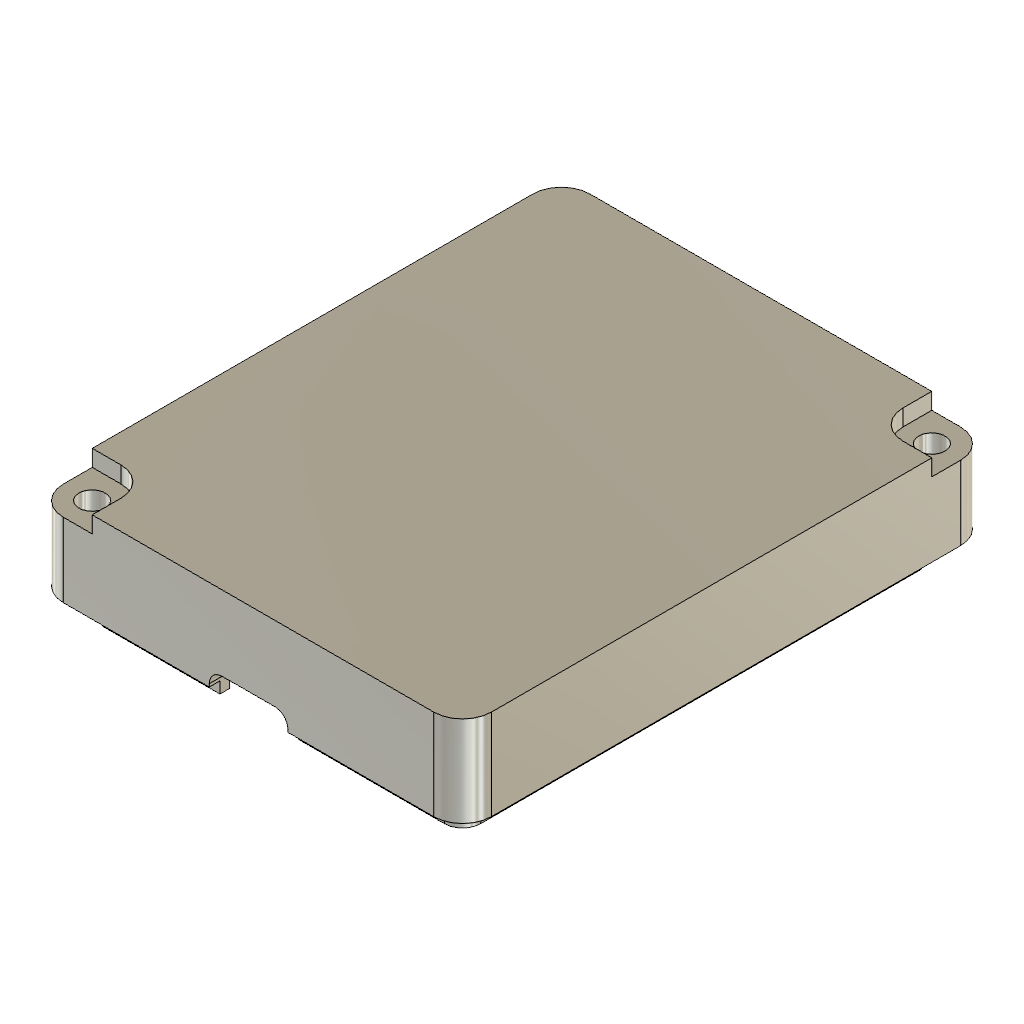
enclosure-Nov13 (Autodesk Fusion 360 archive; units mm, degrees)
design "lid-usb"
Autodesk Fusion 360 part; units mm, degrees
sketch "Sketch1" plane through (0, 0, 0) normal (0, 0, 1) x (1, 0, 0)
  circle A0 centre (22.5, -0.75) radius 1.55
  line L0 (22.5, -58.75) -> (-19, -58.75)
  arc A1 (-19, -57.75) -> (-22.5, -54.25) centre (-22.5, -57.75) ccw
  arc A2 (23.5, -57.75) -> (22.5, -58.75) centre (22.5, -57.75) cw
  arc A3 (-23.5, -0.75) -> (-22.5, 0.25) centre (-22.5, -0.75) cw
  arc A4 (19, -0.75) -> (22.5, -4.25) centre (22.5, -0.75) ccw
  line L1 (-22.5, 0.25) -> (19, 0.25)
  line L2 (22.5, -4.25) -> (23.5, -4.25)
  line L3 (-22.5, -54.25) -> (-23.5, -54.25)
  line L4 (-23.5, -54.25) -> (-23.5, -0.75)
  line L5 (19, 0.25) -> (19, -0.75)
  line L6 (-19, -58.75) -> (-19, -57.75)
  line L7 (23.5, -4.25) -> (23.5, -57.75)
  line L8 (22.5, 2.75) -> (-22.5, 2.75)
  arc A5 (26, -0.75) -> (22.5, 2.75) centre (22.5, -0.75) ccw
  arc A6 (-22.5, 2.75) -> (-26, -0.75) centre (-22.5, -0.75) ccw
  line L9 (-26, -0.75) -> (-26, -57.75)
  arc A7 (-26, -57.75) -> (-22.5, -61.25) centre (-22.5, -57.75) ccw
  arc A8 (22.5, -61.25) -> (26, -57.75) centre (22.5, -57.75) ccw
  line L10 (26, -57.75) -> (26, -0.75)
  line L11 (-22.5, -61.25) -> (22.5, -61.25)
  circle A9 centre (-22.5, -57.75) radius 1.55
  line L12 (-24.8, -0.75) -> (-24.8, -57.75)
  arc A10 (-22.5, 1.55) -> (-24.8, -0.75) centre (-22.5, -0.75) ccw
  line L13 (24.8, -57.75) -> (24.8, -0.75)
  line L14 (22.5, 1.55) -> (-22.5, 1.55)
  line L15 (-22.5, -60.05) -> (22.5, -60.05)
  arc A11 (22.5, -60.05) -> (24.8, -57.75) centre (22.5, -57.75) ccw
  arc A12 (-24.8, -57.75) -> (-22.5, -60.05) centre (-22.5, -57.75) ccw
  arc A13 (24.8, -0.75) -> (22.5, 1.55) centre (22.5, -0.75) ccw
  line L16 (23.5, -4.25) -> (24.8, -4.25)
  line L17 (19, 0.25) -> (19, 1.55)
  line L18 (-19, -58.75) -> (-19, -60.05)
  line L19 (-23.5, -54.25) -> (-24.8, -54.25)
  line L20 (5, -60.05) -> (5, -58.75)
  line L21 (-5, -60.05) -> (-5, -58.75)
  line L22 (24.8, -4.25) -> (26, -4.25)
  line L23 (19, 1.55) -> (19, 2.75)
  line L24 (-19, -60.05) -> (-19, -61.25)
  line L25 (-24.8, -54.25) -> (-26, -54.25)
  line L26 (-17, -58.75) -> (-17, -57.75)
  arc A14 (-17, -57.75) -> (-22.5, -52.25) centre (-22.5, -57.75) ccw
  line L27 (-22.5, -52.25) -> (-23.5, -52.25)
  line L28 (17, 0.25) -> (17, -0.75)
  arc A15 (17, -0.75) -> (22.5, -6.25) centre (22.5, -0.75) ccw
  line L29 (22.5, -6.25) -> (23.5, -6.25)
  point P0 (0, -60.05)
  dimension "d22" = 2
  dimension "d23" = 2
  constraint coincident L13 L16.end
  constraint coincident L10 L22.end
  constraint perpendicular L10 L22
  constraint coincident L8 L23.end
  constraint perpendicular L8 L23
  constraint coincident L11 L24.end
  constraint perpendicular L11 L24
  constraint coincident L9 L25.end
  constraint perpendicular L9 L25
extrude "Extrude1" add sketch "Sketch1" against normal blind 2 contours A0 | L0 A2 L7 L13 L15 A11 L16 L20 | L0 A2 A3 L1 L4 L7 L26 A14 L27 L28 A15 L29 | L0 L15 L20 L21 | L0 L15 L18 L21 | A8 L10 L11 L13 L15 A11 L22 L24 | A4 L1 L2 L5 L7 L28 A15 L29 | L0 A1 L3 L4 L6 L26 A14 L27 | A4 L2 L5 L13 L14 A13 L16 L17 | A1 L3 L6 L12 L15 A12 L18 L19 | L9 A7 L11 L12 L15 A12 L24 L25 | L8 A5 L10 L13 L14 A13 L22 L23 | A3 L1 L4 L12 A10 L14 L17 L19 | L8 A6 L9 L12 A10 L14 L23 L25 | A9
extrude "Extrude3" add sketch "Sketch1" against normal blind 11 contours L0 A2 L7 L13 L15 A11 L16 L20 | L0 L15 L20 L21 | L0 L15 L18 L21 | A8 L10 L11 L13 L15 A11 L22 L24 | A4 L2 L5 L13 L14 A13 L16 L17 | A1 L3 L6 L12 L15 A12 L18 L19 | L9 A7 L11 L12 L15 A12 L24 L25 | L8 A5 L10 L13 L14 A13 L22 L23 | A3 L1 L4 L12 A10 L14 L17 L19 | L8 A6 L9 L12 A10 L14 L23 L25
hole "Hole1" at (-22.5, -57.75, 0) at (22.5, -0.75, 0) direction (0, 0, -1) diameter 3.2 depth 12 tip angle 118
sketch "Sketch4" plane through (0, 0, -11) normal (0, 0, -1) x (1, 0, 0)
  circle A0 centre (-22.5, 57.75) radius 1.6
  circle A1 centre (22.5, 0.75) radius 1.6
  line L0 (23.5, 4.25) -> (22.5, 4.25)
  arc A2 (22.5, 4.25) -> (19, 0.75) centre (22.5, 0.75) ccw
  line L1 (19, 0.75) -> (19, -0.25)
  line L2 (19, -0.25) -> (-22.5, -0.25)
  arc A3 (-23.5, 0.75) -> (-22.5, -0.25) centre (-22.5, 0.75) ccw
  line L3 (-23.5, 0.75) -> (-23.5, 54.25)
  line L4 (-23.5, 54.25) -> (-22.5, 54.25)
  arc A4 (-22.5, 54.25) -> (-19, 57.75) centre (-22.5, 57.75) ccw
  line L5 (-19, 57.75) -> (-19, 58.75)
  line L6 (-19, 58.75) -> (22.5, 58.75)
  arc A5 (23.5, 57.75) -> (22.5, 58.75) centre (22.5, 57.75) ccw
  line L7 (23.5, 57.75) -> (23.5, 4.25)
  line L8 (22.5, 61.25) -> (-22.5, 61.25)
  arc A6 (-22.5, 61.25) -> (-26, 57.75) centre (-22.5, 57.75) ccw
  line L9 (-26, 57.75) -> (-26, 0.75)
  arc A7 (-26, 0.75) -> (-22.5, -2.75) centre (-22.5, 0.75) ccw
  line L10 (-22.5, -2.75) -> (22.5, -2.75)
  arc A8 (22.5, -2.75) -> (26, 0.75) centre (22.5, 0.75) ccw
  line L11 (26, 0.75) -> (26, 57.75)
  arc A9 (26, 57.75) -> (22.5, 61.25) centre (22.5, 57.75) ccw
  line L12 (-24.7, 57.75) -> (-24.7, 0.75)
  arc A10 (-24.7, 0.75) -> (-22.5, -1.45) centre (-22.5, 0.75) ccw
  line L13 (-22.5, -1.45) -> (22.5, -1.45)
  arc A11 (22.5, -1.45) -> (24.7, 0.75) centre (22.5, 0.75) ccw
  line L14 (24.7, 0.75) -> (24.7, 57.75)
  arc A12 (24.7, 57.75) -> (22.5, 59.95) centre (22.5, 57.75) ccw
  line L15 (22.5, 59.95) -> (-22.5, 59.95)
  arc A13 (-22.5, 59.95) -> (-24.7, 57.75) centre (-22.5, 57.75) ccw
  line L16 (-19, 58.75) -> (-19, 59.95)
  line L17 (-23.5, 54.25) -> (-24.7, 54.25)
  line L18 (19, -0.25) -> (19, -1.45)
  line L19 (23.5, 4.25) -> (24.7, 4.25)
  dimension "d27" = -1.3
  constraint coincident L5.end L6.start
  constraint coincident L15 L16.end
  constraint perpendicular L15 L16
  constraint coincident L3.end L4.start
  constraint coincident L12 L17.end
  constraint perpendicular L12 L17
  constraint coincident L1.end L2.start
  constraint coincident L13 L18.end
  constraint perpendicular L13 L18
  constraint coincident L0.start L7.end
  constraint coincident L14 L19.end
  constraint perpendicular L14 L19
extrude "Extrude9" add sketch "Sketch4" along normal blind 1.4 contours L6 A5 L7 L14 A12 L15 L16 L19 | L2 A3 L3 L12 A10 L13 L17 L18
sketch "Sketch5" plane through (0, -59.95, 0) normal (0, -1, 0) x (1, 0, 0)
  line L0 (22.5, -11) -> (-19, -11)
  line L1 (-19, -11) -> (-19, -12.4)
  line L2 (-19, -12.4) -> (22.5, -12.4)
  line L3 (22.5, -12.4) -> (22.5, -11)
  line L4 (4.7606, -11) -> (22.5, -11)
  line L5 (22.5, -11) -> (22.5, -12.4)
  line L6 (22.5, -12.4) -> (4.7606, -12.4)
  line L7 (4.7606, -12.4) -> (4.7606, -11)
  constraint horizontal L4
  constraint vertical L5
  constraint horizontal L6
  constraint vertical L7
  constraint coincident L2 L3.start
  constraint coincident L0.start L3.end
sketch "Sketch2" plane through (0, 2.75, 0) normal (0, 1, 0) x (-1, 0, 0)
  line L0 (22.5, 0) -> (-22.5, 0)
  line L1 (-22.5, 0) -> (-22.5, -11)
  line L2 (-22.5, -11) -> (22.5, -11)
  line L3 (22.5, -11) -> (22.5, 0)
  line L4 (-3.5, -10.5) -> (3.5, -10.5)
  line L5 (3.5, -10.5) -> (3.5, -11)
  line L6 (3.5, -11) -> (-3.5, -11)
  line L7 (-3.5, -11) -> (-3.5, -10.5)
  line L8 (-5, -12.5) -> (-5, -9)
  line L9 (-5, -9) -> (5, -9)
  line L10 (5, -9) -> (5, -12.5)
  line L11 (5, -12.5) -> (-5, -12.5)
  point P0 (0, -11)
  dimension "d12" = 7
  dimension "d13" = 0.5
  dimension "d14" = -1.5
  constraint midpoint L2 P0
  constraint horizontal L4
  constraint vertical L5
  constraint horizontal L6
  constraint vertical L7
  constraint midpoint P0 L6
  measures "d12" distance of L4.start L4.end
  measures "d13" distance of L4.start L6.end
extrude "Extrude5" cut sketch "Sketch2" against normal blind 7 contours L2 L6 L8 L10 L11 | L2 L4 L5 L6 L7
extrude "Extrude6" add sketch "Sketch2" against normal blind 3.7 contours L2 L4 L5 L7 L8 L9 L10
chamfer "Chamfer1" distance 0.4 angle 45 3 edges at (0, 2.75, -10.5) (3.5, 2.75, -10.75) (-3.5, 2.75, -10.75) tangent chain off
extrude "Extrude7" cut sketch "Sketch1" against normal blind 2 contours A4 L2 L5 L13 L14 A13 L16 L17 | A1 L3 L6 L12 L15 A12 L18 L19 | L9 A7 L11 L12 L15 A12 L24 L25 | L8 A5 L10 L13 L14 A13 L22 L23
extrude "Extrude8" add sketch "Sketch1" against normal blind 4 contours A4 L1 L2 L5 L7 L28 A15 L29 | L0 A1 L3 L4 L6 L26 A14 L27
sketch "Sketch6" plane through (0, -61.25, 0) normal (0, -1, 0) x (1, 0, 0)
  line L0 (-19, 0) -> (-19, -2)
  line L1 (-19, -2) -> (-22.5, -2)
  line L2 (-22.5, -2) -> (-22.5, -11)
  line L3 (-22.5, -11) -> (22.5, -11)
  line L4 (22.5, -11) -> (22.5, 0)
  line L5 (22.5, 0) -> (-19, 0)
  line L6 (-3.22, -9.395) -> (3.22, -9.395)
  line L7 (4.47, -10.645) -> (4.47, -11)
  line L8 (4.47, -11) -> (-4.47, -11)
  line L9 (-4.47, -11) -> (-4.47, -10.645)
  arc A0 (-3.22, -9.395) -> (-4.47, -10.645) centre (-3.22, -10.645) ccw
  arc A1 (4.47, -10.645) -> (3.22, -9.395) centre (3.22, -10.645) ccw
  line L10 (-4.77, -11.3) -> (-4.77, -10.645)
  arc A2 (-3.22, -9.095) -> (-4.77, -10.645) centre (-3.22, -10.645) ccw
  line L11 (-3.22, -9.095) -> (3.22, -9.095)
  arc A3 (4.77, -10.645) -> (3.22, -9.095) centre (3.22, -10.645) ccw
  line L12 (4.77, -10.645) -> (4.77, -11.3)
  line L13 (4.77, -11.3) -> (-4.77, -11.3)
  line L14 (-4.77, -11.3) -> (4.77, -11.3)
  line L15 (4.77, -11.3) -> (4.77, -12.6116)
  line L16 (4.77, -12.6116) -> (-4.77, -12.6116)
  line L17 (-4.77, -12.6116) -> (-4.77, -11.3)
  point P0 (-4.47, -9.395)
  point P1 (4.47, -9.395)
  point P2 (0, -11)
  dimension "d32" = 8.94
  dimension "d33" = 1.605
  dimension "d34" = 1.25
  dimension "d35" = 0.3
  constraint horizontal L6
  constraint vertical L7
  constraint horizontal L8
  constraint vertical L9
  constraint midpoint L8 P2
  constraint coincident P0 L6
  constraint coincident P0 L9
  constraint tangent L6 A0
  constraint tangent L9 A0
  constraint coincident P1 L6
  constraint coincident P1 L7
  constraint tangent L6 A1
  constraint tangent L7 A1
  constraint equal A0 A1
  constraint horizontal L14
  constraint vertical L15
  constraint horizontal L16
  constraint vertical L17
  measures "d32" distance of P0 P1
  measures "d33" distance of P0 L8.end
  measures "d34" radius of A0
extrude "Extrude11" cut sketch "Sketch6" against normal blind 3.5 contours L3 L8 L10 L12 L13 L14 | L3 L6 L7 L9 A0 A1 L10 A2 L11 A3 L12 | L3 L6 L7 L8 L9 A0 A1 | L13 L14 L15 L16 L17
chamfer "Chamfer2" distance 1 angle 45 6 edges at (18.6109, -4.6391, -4) (17, -0.25, -4) (23, -6.25, -4) (-18.6109, -53.8609, -4) (-17, -58.25, -4) (-23, -52.25, -4) tangent chain off
chamfer "Chamfer3" distance 1.2 angle 45 1 edges at (0, 0.25, -9) tangent chain off
sketch "Sketch7" plane through (0, 0, -2) normal (0, 0, -1) x (1, 0, 0)
  line L0 (17, -0.25) -> (17, 0.75)
  arc A0 (22.5, 6.25) -> (17, 0.75) centre (22.5, 0.75) ccw
  line L1 (22.5, 6.25) -> (23.5, 6.25)
  line L2 (23.5, 6.25) -> (23.5, 57.75)
  arc A1 (23.5, 57.75) -> (22.5, 58.75) centre (22.5, 57.75) ccw
  line L3 (22.5, 58.75) -> (-17, 58.75)
  line L4 (-17, 58.75) -> (-17, 57.75)
  arc A2 (-22.5, 52.25) -> (-17, 57.75) centre (-22.5, 57.75) ccw
  line L5 (-22.5, 52.25) -> (-23.5, 52.25)
  line L6 (-23.5, 52.25) -> (-23.5, 0.75)
  arc A3 (-23.5, 0.75) -> (-22.5, -0.25) centre (-22.5, 0.75) ccw
  line L7 (-22.5, -0.25) -> (17, -0.25)
  circle A4 centre (10.16, 26.05) radius 2.5
  circle A5 centre (-10.16, 26.05) radius 2.5
  line L8 (23.5, 4.25) -> (23.5, 57.75)
  line L9 (-23.5, 54.25) -> (-23.5, 0.75)
  circle A6 centre (10.16, 26.05) radius 1.05
  circle A7 centre (-10.16, 26.05) radius 1.05
  circle A8 centre (10.16, 6.75) radius 2.5
  circle A9 centre (10.16, 6.75) radius 1.05
  circle A10 centre (-10.16, 6.75) radius 2.5
  circle A11 centre (-10.16, 6.75) radius 1.05
  point P0 (5, 60.05)
  dimension "d39" = 5
  dimension "d40" = 5
  dimension "d41" = 34
  dimension "d42" = 2.1
  dimension "d43" = 2.1
  dimension "d46" = 5
  dimension "d47" = 2.1
  dimension "d48" = 5
  dimension "d49" = 2.1
  dimension "d50" = 7
  dimension "d51" = 20.32
  dimension "d52" = 10.16
  dimension "d55" = 20.32
  constraint horizontal A4.centre A5.centre
  constraint concentric A4 A6
  constraint concentric A5 A7
  constraint concentric A8 A9
  constraint concentric A10 A11
  constraint horizontal A8.centre A10.centre
  constraint vertical A4.centre A8.centre
  measures "d39" diameter of A4
  measures "d40" diameter of A5
  measures "d41" vertical distance of A4.centre P0
  measures "d42" diameter of A6
  measures "d43" diameter of A7
  measures "d46" diameter of A8
  measures "d47" diameter of A9
  measures "d48" diameter of A10
  measures "d49" diameter of A11
  measures "d50" distance of L7 A8.centre
  measures "d51" distance of A8.centre A10.centre
  measures "d52" horizontal distance of origin A8.centre
  measures "d55" distance of A5.centre A4.centre
extrude "Extrude12" add sketch "Sketch7" along normal blind 5 contours A4 | A5
extrude "Extrude13" add sketch "Sketch7" along normal blind 5 contours A8 | A10
move_face "OffsetFaces1" offset -0.1 1 faces at (-5, 0.65, -11.4667)
move_face "OffsetFaces2" offset -0.1 1 faces at (5, 1.05, -11.9333)
sketch "Sketch8" plane through (0, 0, -2) normal (0, 0, 1) x (-1, 0, 0)
  circle A0 centre (-22.5, 0.75) radius 1.6
  line L0 (-19, -2.75) -> (-19, 0.75)
  arc A1 (-19, 0.75) -> (-22.5, 4.25) centre (-22.5, 0.75) ccw
  line L1 (-22.5, 4.25) -> (-23.5, 4.25)
  line L2 (-23.5, 4.25) -> (-24.8, 4.25)
  line L3 (-24.8, 4.25) -> (-26, 4.25)
  line L4 (-26, 4.25) -> (-26, 0.75)
  arc A2 (-26, 0.75) -> (-22.5, -2.75) centre (-22.5, 0.75) ccw
  line L5 (-22.5, -2.75) -> (-19, -2.75)
  line L6 (-19.5, -2.75) -> (-19.5, 0.75)
  arc A3 (-19.5, 0.75) -> (-22.5, 3.75) centre (-22.5, 0.75) ccw
  line L7 (-22.5, 3.75) -> (-23.5, 3.75)
  line L8 (-23.5, 3.75) -> (-24.8, 3.75)
  line L9 (-24.8, 3.75) -> (-26, 3.75)
  dimension "d56" = -0.5
extrude "Extrude14" [suppressed]

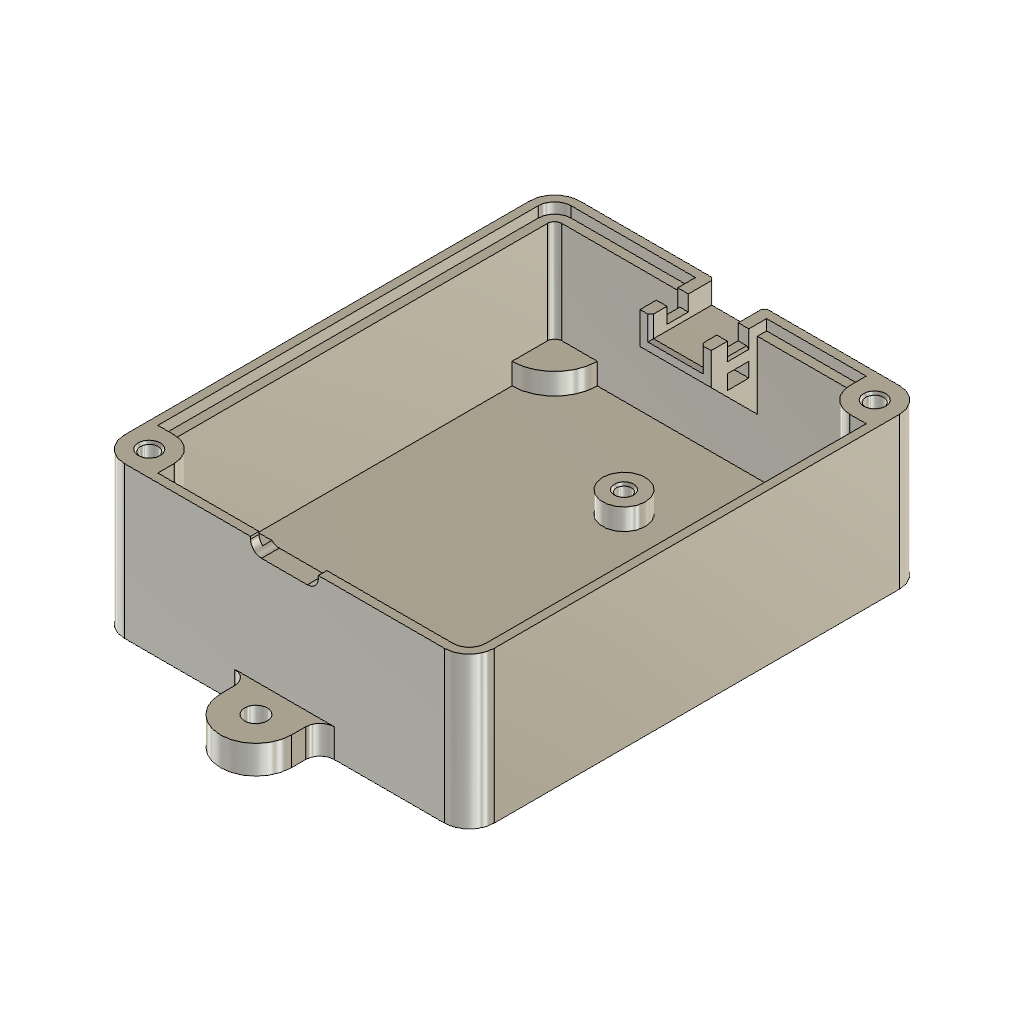
design "base-usb"
Autodesk Fusion 360 part; units mm, degrees
sketch "Sketch1" plane through (0, 0, 0) normal (0, 0, 1) x (1, 0, 0)
  line L0 (-23.5, 58.75) -> (23.5, 58.75)
  line L1 (23.5, 58.75) -> (23.5, -0.25)
  line L2 (23.5, -0.25) -> (-23.5, -0.25)
  line L3 (-23.5, -0.25) -> (-23.5, 58.75)
  line L4 (-26, -2.75) -> (-26, 61.25)
  line L5 (-26, 61.25) -> (26, 61.25)
  line L6 (26, 61.25) -> (26, -2.75)
  line L7 (26, -2.75) -> (-26, -2.75)
  circle A0 centre (0, 2.5) radius 3
  circle A1 centre (0, 2.5) radius 1.05
  line L8 (-3, 2.5) -> (-3, -0.25)
  line L9 (3, 2.5) -> (3, -0.25)
  circle A2 centre (0, -6.75) radius 5
  line L10 (-5, -6.75) -> (-5, -2.75)
  line L11 (5, -6.75) -> (5, -2.75)
  circle A3 centre (0, 65.25) radius 5
  line L12 (-5, 65.25) -> (-5, 61.25)
  line L13 (5, 65.25) -> (5, 61.25)
  circle A4 centre (0, 45) radius 3
  circle A5 centre (0, 45) radius 1.05
  circle A6 centre (-22.5, 57.75) radius 3.5
  circle A7 centre (22.5, 57.75) radius 3.5
  circle A8 centre (-22.5, 0.75) radius 3.5
  circle A9 centre (22.5, 0.75) radius 3.5
  arc A10 (-16, -0.25) -> (-23.5, 7.25) centre (-23.5, -0.25) ccw
  arc A11 (16, 58.75) -> (23.5, 51.25) centre (23.5, 58.75) ccw
  circle A12 centre (-20.5, 40) radius 3
  circle A13 centre (20.5, 40) radius 3
  line L14 (-20.5, 43) -> (-23.5, 43)
  line L15 (-20.5, 37) -> (-23.5, 37)
  line L16 (20.5, 43) -> (23.5, 43)
  line L17 (20.5, 37) -> (23.7017, 37)
  arc A14 (-23.5, 52.75) -> (-17.5, 58.75) centre (-23.5, 58.75) ccw
  arc A15 (23.5, 5.75) -> (17.5, -0.25) centre (23.5, -0.25) ccw
  circle A16 centre (-22.5, 0.75) radius 1.25
  circle A17 centre (22.5, 57.75) radius 1.25
  line L18 (19, 57.75) -> (19, 61.25)
  line L19 (22.5, 54.25) -> (26, 54.25)
  line L20 (-22.5, 4.25) -> (-26, 4.25)
  line L21 (-19, 0.75) -> (-19, -2.75)
  point P0 (0, -0.25)
  dimension "d1" = 47
  dimension "d2" = 59
  dimension "d3" = 0.25
  dimension "d4" = -2.5
  dimension "d5" = 6
  dimension "d6" = 2.1
  dimension "d7" = 2.5
  dimension "d8" = 10
  dimension "d9" = 4
  dimension "d10" = 10
  dimension "d11" = 72
  dimension "d12" = 6
  dimension "d13" = 2.1
  dimension "d14" = 45
  dimension "d15" = 3.5
  dimension "d16" = 3.5
  dimension "d17" = 3.5
  dimension "d18" = 3.5
  dimension "d19" = 7.5
  dimension "d20" = 7.5
  dimension "d21" = 6
  dimension "d23" = 6
  dimension "d24" = 40
  dimension "d25" = 6
  dimension "d26" = 6
  dimension "d29" = 2.5
  dimension "d30" = 2.5
  constraint horizontal L0
  constraint vertical L1
  constraint horizontal L2
  constraint vertical L3
  constraint midpoint L2 P0
  constraint vertical origin P0
  constraint concentric A0 A1
  constraint coincident A0 L8.start
  constraint coincident L2 L8.end
  constraint perpendicular L2 L8
  constraint coincident A0 L9.start
  constraint coincident L2 L9.end
  constraint perpendicular L2 L9
  constraint tangent A0 L8
  constraint tangent A0 L9
  constraint coincident A2 L10.start
  constraint coincident L7 L10.end
  constraint tangent A2 L10
  constraint coincident A2 L11.start
  constraint coincident L7 L11.end
  constraint tangent A2 L11
  constraint vertical L10
  constraint vertical L11
  constraint vertical A2.centre A3.centre
  constraint vertical origin A2.centre
  constraint vertical origin A0.centre
  constraint coincident A3 L12.start
  constraint coincident L5 L12.end
  constraint perpendicular L5 L12
  constraint coincident A3 L13.start
  constraint coincident L5 L13.end
  constraint perpendicular L5 L13
  constraint tangent A3 L12
  constraint tangent A3 L13
  constraint concentric A4 A5
  constraint vertical A0.centre A4.centre
  constraint tangent L5 A6
  constraint tangent L4 A6
  constraint tangent L5 A7
  constraint tangent L6 A7
  constraint tangent L4 A8
  constraint tangent L7 A8
  constraint tangent L7 A9
  constraint tangent L6 A9
  constraint coincident L2 A10.start
  constraint coincident L2.end L3.start
  constraint coincident L0 A11.start
  constraint coincident L0.end L1.start
  constraint horizontal A12.centre A13.centre
  constraint tangent L3 A12
  constraint tangent L1 A13
  constraint coincident A12 L14.start
  constraint coincident L3 L14.end
  constraint tangent A12 L14
  constraint coincident A12 L15.start
  constraint coincident L3 L15.end
  constraint tangent A12 L15
  constraint horizontal L14
  constraint horizontal L15
  constraint coincident A13 L16.start
  constraint coincident L1 L16.end
  constraint tangent A13 L16
  constraint coincident A13 L17.start
  constraint tangent A13 L17
  constraint horizontal L16
  constraint horizontal L17
  constraint coincident L0 A14.end
  constraint coincident L0.start L3.end
  constraint coincident L1 A15.start
  constraint coincident L1.end L2.start
  constraint concentric A8 A16
  constraint concentric A7 A17
  constraint coincident L3 A10.end
  constraint coincident L2 A15.end
  constraint coincident A7 L18.start
  constraint coincident L5 L18.end
  constraint perpendicular L5 L18
  constraint coincident A7 L19.start
  constraint coincident L6 L19.end
  constraint perpendicular L6 L19
  constraint tangent A7 L19
  constraint tangent A7 L18
  constraint coincident A8 L20.start
  constraint coincident L4 L20.end
  constraint perpendicular L4 L20
  constraint coincident A8 L21.start
  constraint coincident L7 L21.end
  constraint tangent A8 L21
  constraint perpendicular L7 L21
  constraint tangent A8 L20
  measures "d1" distance of L0.start L0.end
  measures "d2" distance of L0.start L2.end
  measures "d3" distance of origin P0
  measures "d5" diameter of A0
  measures "d6" diameter of A1
  measures "d7" vertical distance of origin A0.centre
  measures "d8" diameter of A2
  measures "d9" distance of L7 A2.centre
  measures "d10" diameter of A3
  measures "d11" distance of A2.centre A3.centre
  measures "d12" diameter of A4
  measures "d13" diameter of A5
  measures "d14" distance of origin A4.centre
  measures "d15" radius of A6
  measures "d16" radius of A7
  measures "d17" radius of A8
  measures "d18" radius of A9
  measures "d19" radius of A10
  measures "d20" radius of A11
  measures "d21" diameter of A12
  measures "d23" diameter of A13
  measures "d24" vertical distance of origin A12.centre
  measures "d25" radius of A14
  measures "d26" radius of A15
  measures "d29" diameter of A16
  measures "d30" diameter of A17
extrude "Extrude1" add sketch "Sketch1" along normal blind 2.5 contours L0 L5 A3 A6 L18 | L0 L3 A6 A14 | L0 L1 L2 L3 A0 L8 L9 A10 A11 A12 A13 L14 L15 L16 L17 A14 A15 | L0 L1 A7 A11 L18 L19 | L0 L3 A6 | L0 L3 A6 | L3 L4 A6 L20 | L0 L5 A7 L18 | L0 A7 L18 | L1 L6 A9 L19 | L3 A12 L14 | L0 L1 A7 A17 | L0 L1 A7 A17 | L1 A13 L16 | L1 A7 L19 | L1 L6 A7 L19 | L5 A3 L12 | L3 A12 L15 | A12 | L0 A17 | L0 L1 A17 | L5 A3 L13 | A13 | L1 A13 L17 | L5 A3 | L5 A3 | L3 L4 A8 L20 | L0 L1 A17 | L1 A17 | L1 L2 A9 | L2 L3 A8 A16 | L3 A8 L20 | L2 L3 A8 A10 L20 L21 | L1 L2 A9 A15 | L1 L2 A9 | L2 L7 A0 A2 A9 L21 | L2 L3 A8 A16 | L2 L7 A8 L21 | L7 A2 L11 | L2 L3 A16 | L3 A16 | L2 A8 L21 | L2 A0 L8 | L2 A0 L9 | L7 A2 | L7 A2 | L2 L3 A16 | L7 A2 L10 | L2 A16 | L2 A0 | L2 A0 | A1 | A4 | A5
extrude "Extrude2" add sketch "Sketch1" along normal blind 21.3 contours L0 L5 A3 A6 L18 | L0 L3 A6 | L3 L4 A6 L20 | L0 L5 A7 L18 | L0 A7 L18 | L1 L6 A9 L19 | L0 L1 A7 A17 | L0 L1 A7 A17 | L1 A7 L19 | L1 L6 A7 L19 | L0 A17 | L0 L1 A17 | L5 A3 | L3 L4 A8 L20 | L0 L1 A17 | L1 A17 | L1 L2 A9 | L2 L3 A8 A16 | L3 A8 L20 | L2 L7 A0 A2 A9 L21 | L2 L3 A8 A16 | L2 L7 A8 L21 | L2 L3 A16 | L3 A16 | L2 A8 L21 | L7 A2 | L2 L3 A16 | L2 A16 | L2 A0 picked at (-23.6552, 55.9059) picked at (-0.7998, 61.1211) picked at (23.6552, 2.5941) picked at (0.1191, -2.4209) picked at (-0.2707, -0.296)
extrude "Extrude3" add sketch "Sketch1" along normal blind 4 contours L5 A3 L12 | L5 A3 L13 | L5 A3 | L7 A2 L11 | L7 A2 | L7 A2 L10 picked at (1.0391, 63.8864) picked at (-0.2042, -8.4849)
extrude "Extrude4" add sketch "Sketch1" along normal blind 5.5 contours L0 L3 A6 A14 | L0 L1 A7 A11 L18 L19 | L0 L3 A6 | L0 A7 L18 | L1 A7 L19 | L3 A8 L20 | L2 L3 A8 A10 L20 L21 | L1 L2 A9 A15 | L1 L2 A9 | L2 A8 L21 | L2 A0 L8 | L2 A0 L9 | L2 A0 | A4 picked at (-21.1905, 56.4348) picked at (21.1877, 2.0623) picked at (0.0262, 0.3176)
extrude "Extrude5" cut sketch "Sketch1" along normal blind 25 from surface at 1 contours L0 A17 | L0 L1 A17 | L1 A17 | L2 L3 A16 | L3 A16 | L2 A16 | A1 | A5 picked at (22.6035, 57.8813) picked at (-22.4882, 0.523)
fillet "Fillet1" radius 1 2 edges at (-23.5, 58.75, 13.4) (23.5, -0.25, 13.4)
hole "Hole1" at (0, -6.75, 0) at (0, 65.25, 0) direction (0, 0, 1) diameter 3.2 depth 10 tip angle 118
chamfer "Chamfer1" distance 0.3 angle 45 4 edges at (-0.9789, 45.3797, 5.5) (-23.6654, 1.202, 21.3) (21.3346, 58.202, 21.3) (-0.9789, 2.8797, 5.5) tangent chain off
sketch "Sketch7" plane through (0, 0, 21.3) normal (0, 0, 1) x (-1, 0, 0)
  circle A0 centre (22.5, -0.75) radius 1.55
  arc A1 (19, -0.75) -> (22.5, -4.25) centre (22.5, -0.75) ccw
  line L0 (22.5, -4.25) -> (23.5, -4.25)
  line L1 (23.5, -4.25) -> (23.5, -57.75)
  arc A2 (22.5, -58.75) -> (23.5, -57.75) centre (22.5, -57.75) ccw
  line L2 (22.5, -58.75) -> (-19, -58.75)
  line L3 (-19, -58.75) -> (-19, -57.75)
  arc A3 (-19, -57.75) -> (-22.5, -54.25) centre (-22.5, -57.75) ccw
  line L4 (-22.5, -54.25) -> (-23.5, -54.25)
  line L5 (-23.5, -54.25) -> (-23.5, -0.75)
  arc A4 (-22.5, 0.25) -> (-23.5, -0.75) centre (-22.5, -0.75) ccw
  line L6 (-22.5, 0.25) -> (19, 0.25)
  line L7 (19, 0.25) -> (19, -0.75)
  arc A5 (22.5, -61.25) -> (26, -57.75) centre (22.5, -57.75) ccw
  line L8 (26, -57.75) -> (26, -0.75)
  arc A6 (26, -0.75) -> (22.5, 2.75) centre (22.5, -0.75) ccw
  line L9 (22.5, 2.75) -> (-22.5, 2.75)
  arc A7 (-22.5, 2.75) -> (-26, -0.75) centre (-22.5, -0.75) ccw
  line L10 (-26, -0.75) -> (-26, -57.75)
  arc A8 (-26, -57.75) -> (-22.5, -61.25) centre (-22.5, -57.75) ccw
  line L11 (-22.5, -61.25) -> (22.5, -61.25)
  circle A9 centre (-22.5, -57.75) radius 1.55
  line L12 (22.5, 1.55) -> (-22.5, 1.55)
  arc A10 (-22.5, 1.55) -> (-24.8, -0.75) centre (-22.5, -0.75) ccw
  line L13 (-24.8, -0.75) -> (-24.8, -57.75)
  arc A11 (-24.8, -57.75) -> (-22.5, -60.05) centre (-22.5, -57.75) ccw
  line L14 (-22.5, -60.05) -> (22.5, -60.05)
  arc A12 (22.5, -60.05) -> (24.8, -57.75) centre (22.5, -57.75) ccw
  line L15 (24.8, -57.75) -> (24.8, -0.75)
  arc A13 (24.8, -0.75) -> (22.5, 1.55) centre (22.5, -0.75) ccw
  line L16 (23.5, -4.25) -> (24.8, -4.25)
  line L17 (19, 0.25) -> (19, 1.55)
  line L18 (-19, -58.75) -> (-19, -60.05)
  line L19 (-23.5, -54.25) -> (-24.8, -54.25)
  line L20 (5, -60.05) -> (5, -58.75)
  line L21 (-5, -60.05) -> (-5, -58.75)
  point P0 (0, -60.05)
  dimension "d73" = -1.2
  dimension "d74" = 10
  dimension "d75" = 5
  constraint coincident L0.end L1.start
  constraint perpendicular L15 L16
  constraint coincident L6.end L7.start
  constraint coincident L12 L17.end
  constraint perpendicular L12 L17
  constraint coincident L2.end L3.start
  constraint coincident L14 L18.end
  constraint perpendicular L14 L18
  constraint coincident L4.end L5.start
  constraint coincident L13 L19.end
  constraint perpendicular L13 L19
  constraint coincident L14 L20.start
  constraint coincident L2 L20.end
  constraint perpendicular L2 L20
  constraint coincident L14 L21.start
  constraint coincident L2 L21.end
  constraint perpendicular L2 L21
  constraint midpoint L14 P0
  constraint coincident L15 L16.end
  measures "d74" horizontal distance of L20.start L21.end
  measures "d75" distance of L20.start P0
sketch "Sketch2" plane through (0, -2.75, 0) normal (0, -1, 0) x (1, 0, 0)
  line L0 (5, 4) -> (5, 0)
  line L1 (5, 0) -> (22.5, 0)
  line L2 (22.5, 0) -> (22.5, 21.3)
  line L3 (22.5, 21.3) -> (-22.5, 21.3)
  line L4 (-22.5, 21.3) -> (-22.5, 0)
  line L5 (-22.5, 0) -> (-5, 0)
  line L6 (-5, 0) -> (-5, 4)
  line L7 (-5, 4) -> (5, 4)
  line L8 (3.22, 19.695) -> (-3.22, 19.695)
  line L9 (-4.47, 20.945) -> (-4.47, 21.655)
  line L10 (-3.22, 22.905) -> (3.22, 22.905)
  line L11 (4.47, 21.655) -> (4.47, 20.945)
  line L12 (4.47, 19.695) -> (-4.47, 22.905) construction
  line L13 (-4.47, 19.695) -> (4.47, 22.905) construction
  arc A0 (-3.22, 22.905) -> (-4.47, 21.655) centre (-3.22, 21.655) ccw
  arc A1 (4.47, 21.655) -> (3.22, 22.905) centre (3.22, 21.655) ccw
  arc A2 (3.22, 19.695) -> (4.47, 20.945) centre (3.22, 20.945) ccw
  arc A3 (-4.47, 20.945) -> (-3.22, 19.695) centre (-3.22, 20.945) ccw
  arc A4 (4.77, 21.655) -> (3.22, 23.205) centre (3.22, 21.655) ccw
  line L14 (-3.22, 23.205) -> (3.22, 23.205)
  arc A5 (-3.22, 23.205) -> (-4.77, 21.655) centre (-3.22, 21.655) ccw
  line L15 (-4.77, 20.945) -> (-4.77, 21.655)
  arc A6 (-4.77, 20.945) -> (-3.22, 19.395) centre (-3.22, 20.945) ccw
  line L16 (3.22, 19.395) -> (-3.22, 19.395)
  arc A7 (3.22, 19.395) -> (4.77, 20.945) centre (3.22, 20.945) ccw
  line L17 (4.77, 21.655) -> (4.77, 20.945)
  point P0 (0, 21.3)
  point P1 (0, 21.3)
  dimension "d44" = 8.94
  dimension "d45" = 3.21
  dimension "d46" = 1.25
  dimension "d47" = 1.25
  dimension "d48" = -0.3
  constraint midpoint L3 P1
  constraint horizontal L8
  constraint perpendicular L8 L9
  constraint parallel L8 L10
  constraint parallel L9 L11
  constraint coincident L12 P1
  constraint coincident L13 P1
  constraint coincident P1 P0
  constraint coincident L12.end L10
  constraint coincident L12.end L9
  constraint tangent L10 A0
  constraint tangent L9 A0
  constraint coincident L13.end L10
  constraint coincident L13.end L11
  constraint tangent L10 A1
  constraint tangent L11 A1
  constraint equal A0 A1
  constraint coincident L12.start L11
  constraint coincident L12.start L8
  constraint tangent L11 A2
  constraint tangent L8 A2
  constraint equal A0 A2
  constraint coincident L13.start L8
  constraint coincident L13.start L9
  constraint tangent L8 A3
  constraint tangent L9 A3
  measures "d44" distance of L12.end L13.end
  measures "d45" distance of L13.start L12.end
  measures "d46" radius of A0
  measures "d47" radius of A3
extrude "Extrude6" cut sketch "Sketch2" against normal blind 13 contours L3 L8 L9 L11 A2 A3 L15 A6 L16 A7 L17 | L3 L8 L9 L11 A2 A3
sketch "Sketch3" plane through (0, 61.25, 0) normal (0, 1, 0) x (-1, 0, 0)
  line L0 (5, 4) -> (5, 0)
  line L1 (5, 0) -> (22.5, 0)
  line L2 (22.5, 0) -> (22.5, 21.3)
  line L3 (22.5, 21.3) -> (-22.5, 21.3)
  line L4 (-22.5, 21.3) -> (-22.5, 0)
  line L5 (-22.5, 0) -> (-5, 0)
  line L6 (-5, 0) -> (-5, 4)
  line L7 (-5, 4) -> (5, 4)
  line L8 (-3.5, 21.3) -> (3.5, 21.3)
  line L9 (3.5, 21.3) -> (3.5, 18.3)
  line L10 (3.5, 18.3) -> (-3.5, 18.3)
  line L11 (-3.5, 18.3) -> (-3.5, 21.3)
  line L12 (5, 22.8) -> (5, 16.8)
  line L13 (5, 16.8) -> (-5, 16.8)
  line L14 (-5, 16.8) -> (-5, 22.8)
  line L15 (-5, 22.8) -> (5, 22.8)
  point P0 (0, 21.3)
  dimension "d51" = 7
  dimension "d52" = 3
  dimension "d53" = -1.5
  constraint midpoint L3 P0
  constraint horizontal L8
  constraint vertical L9
  constraint horizontal L10
  constraint vertical L11
  constraint midpoint P0 L8
  measures "d51" distance of L8.start L8.end
  measures "d52" distance of L8.start L10.end
extrude "Extrude7" cut sketch "Sketch3" against normal blind 5 contours L3 L8 L9 L10 L11
extrude "Extrude8" add sketch "Sketch3" against normal blind 9 contours L3 L9 L10 L11 L12 L13 L14
chamfer "Chamfer2" distance 6.5 angle 45 1 edges at (0, 58.75, 16.8) tangent chain off
ref_plane "WorkPlane1" through (0, 29.25, 10.65) normal (-1, 0, 0) x (0, -1, 0)
sketch "Sketch5" plane through (0, 0, 0) normal (-1, 0, 0) x (0, -1, 0)
  line L0 (-57.55, 17.05) -> (-54.55, 17.05)
  line L1 (-54.55, 17.05) -> (-54.55, 15.3)
  line L2 (-54.55, 15.3) -> (-57.55, 15.3)
  line L3 (-57.55, 15.3) -> (-57.55, 17.05)
  line L4 (-61.25, 18.3) -> (-52.25, 18.3)
  line L5 (-57.55, 18.3) -> (-54.55, 18.3)
  line L6 (-54.55, 18.3) -> (-54.55, 22.3)
  line L7 (-54.55, 22.3) -> (-57.55, 22.3)
  line L8 (-57.55, 22.3) -> (-57.55, 18.3)
  line L9 (-57.55, 19.1) -> (-54.55, 19.1)
  point P0 (-61.25, 18.3)
  dimension "d60" = 3
  dimension "d61" = 1.75
  dimension "d62" = 1.25
  dimension "d63" = 3
  dimension "d64" = 4
  dimension "d65" = 3.7
  dimension "d68" = 0.8
  constraint horizontal L0
  constraint vertical L1
  constraint horizontal L2
  constraint vertical L3
  constraint horizontal L5
  constraint vertical L6
  constraint horizontal L7
  constraint vertical L8
  constraint coincident L4 L5.start
  constraint vertical L0.start L5.start
  constraint coincident L8 L9.start
  constraint coincident L6 L9.end
  constraint perpendicular L6 L9
  measures "d60" distance of L0.start L0.end
  measures "d61" distance of L0.start L2.end
  measures "d62" distance of L0.start L4
  measures "d63" distance of L5.start L5.end
  measures "d64" distance of L5.start L7.end
  measures "d65" distance of L5.start P0
  measures "d68" distance of L5.end L9.end
extrude "Extrude9" cut sketch "Sketch5" along normal mid plane 12 contours L0 L1 L2 L3 | L6 L7 L8 L9
chamfer "Chamfer4" distance 0.3 angle 45 4 edges at (-5, 56.05, 19.1) (-5, 56.05, 17.05) (5, 56.05, 19.1) (5, 56.05, 17.05) tangent chain off
chamfer "Chamfer5" distance 0.4 angle 45 6 edges at (-3.5, 52.25, 19.8) (3.5, 52.25, 19.8) (0, 61.25, 18.3) (-3.5, 61.25, 19.8) (3.5, 61.25, 19.8) (0, 52.25, 18.3) tangent chain off
sketch "Sketch6" plane through (0, 0, 21.3) normal (0, 0, 1) x (-1, 0, 0)
  line L0 (3.5, -60.85) -> (3.9, -61.25)
  line L1 (3.9, -61.25) -> (22.5, -61.25)
  arc A0 (22.5, -61.25) -> (26, -57.75) centre (22.5, -57.75) ccw
  line L2 (26, -57.75) -> (26, -0.75)
  arc A1 (26, -0.75) -> (22.5, 2.75) centre (22.5, -0.75) ccw
  line L3 (22.5, 2.75) -> (4.77, 2.75)
  line L4 (4.77, 2.75) -> (4.77, 0.25)
  line L5 (4.77, 0.25) -> (19, 0.25)
  line L6 (19, 0.25) -> (19, -0.75)
  arc A2 (19, -0.75) -> (22.5, -4.25) centre (22.5, -0.75) ccw
  line L7 (22.5, -4.25) -> (23.5, -4.25)
  line L8 (23.5, -4.25) -> (23.5, -57.75)
  arc A3 (22.5, -58.75) -> (23.5, -57.75) centre (22.5, -57.75) ccw
  line L9 (22.5, -58.75) -> (5, -58.75)
  line L10 (5, -58.75) -> (5, -57.55)
  line L11 (5, -57.55) -> (3.5, -57.55)
  line L12 (3.5, -57.55) -> (3.5, -60.85)
  circle A4 centre (22.5, -0.75) radius 1.55
extrude "Extrude10" cut sketch "Sketch7" against normal blind 1.5 contours L5 A4 L6 L12 A10 L13 L17 L19 | L1 A2 L2 L14 A12 L15 L16 L20 | L2 L14 L18 L21
sketch "Sketch8" plane through (0, -0.25, 0) normal (0, 1, 0) x (-1, 0, 0)
  line L0 (57.75, 19.8) -> (4.25, 19.8)
  line L1 (4.25, 19.8) -> (4.25, 5.5)
  line L2 (4.25, 5.5) -> (7.25, 5.5)
  line L3 (7.25, 5.5) -> (7.25, 2.5)
  line L4 (7.25, 2.5) -> (52.75, 2.5)
  line L5 (52.75, 2.5) -> (52.75, 5.5)
  line L6 (52.75, 5.5) -> (57.75, 5.5)
  line L7 (57.75, 5.5) -> (57.75, 19.8)
  circle A0 centre (-15, 14.5) radius 3.25
  line L8 (19, 19.8) -> (4.2647, 19.8)
  arc A1 (3.22, 19.395) -> (4.2647, 19.8) centre (3.22, 20.945) ccw
  line L9 (3.22, 19.395) -> (-3.22, 19.395)
  arc A2 (-4.2647, 19.8) -> (-3.22, 19.395) centre (-3.22, 20.945) ccw
  line L10 (-4.2647, 19.8) -> (-22.5, 19.8)
  line L11 (-22.5, 19.8) -> (-22.5, 5.5)
  line L12 (-22.5, 5.5) -> (-17.5, 5.5)
  line L13 (-17.5, 5.5) -> (-17.5, 2.5)
  line L14 (-17.5, 2.5) -> (-3, 2.5)
  line L15 (-3, 2.5) -> (-3, 5.5)
  line L16 (-3, 5.5) -> (3, 5.5)
  line L17 (3, 5.5) -> (3, 2.5)
  line L18 (3, 2.5) -> (16, 2.5)
  line L19 (16, 2.5) -> (16, 5.5)
  line L20 (16, 5.5) -> (19, 5.5)
  line L21 (19, 5.5) -> (19, 19.8)
  dimension "d78" = 6.5
  dimension "d79" = 12
  dimension "d85" = 15
  measures "d78" diameter of A0
  measures "d79" distance of L4 A0.centre
  measures "d85" horizontal distance of origin A0.centre
extrude "Extrude11" cut sketch "Sketch8" against normal blind 1.5 contours A0
fillet "Fillet2" radius 2 4 edges at (-5, 61.25, 2) (5, 61.25, 2) (5, -2.75, 2) (-5, -2.75, 2)
